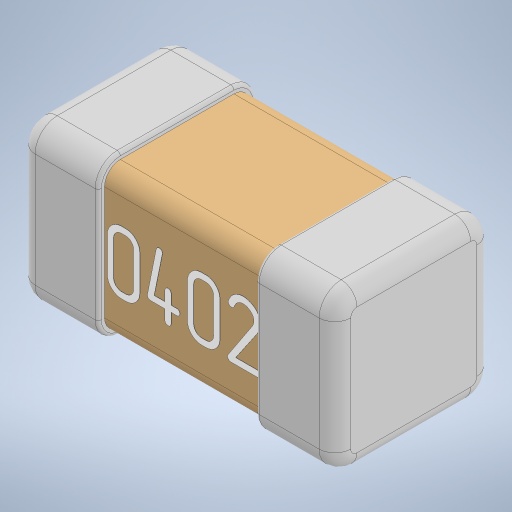
# Autodesk Inventor part: Discrete_Resistors_Ceramic_SMD
Saved by Autodesk Inventor 2024 (Build 280153000, 153)
## iProperties
Created: 2026-11-02
Part Number: Discrete_Resistors_Ceramic_SMD
Material: Generic
Document SubType Name: Modeling
Designer: danil
Density: 1 g/cm^3
Appearance: Default
Mass: 2.84071e-06 g
Surface Area: 0.00232509 cm^2
Volume: 2.84071e-06 cm^3
Author: danil
Autodesk Inventor part; units mm, degrees
ref_plane "YZ Plane" through (0, 0, 0) normal (1, 0, 0) x (0, 1, 0)
ref_plane "XZ Plane" through (0, 0, 0) normal (0, 1, 0) x (-1, 0, 0)
ref_plane "XY Plane" through (0, 0, 0) normal (0, 0, 1) x (1, 0, 0)
sketch "Sketch10" plane through (-0.11, 0.0625, 0) normal (0, 0, 1) x (1, 0, 0)
  line L0 (-0.37, -0.2925) -> (-0.37, 0.1675)
  line L1 (-0.37, 0.1675) -> (0.59, 0.1675)
  line L2 (0.59, 0.1675) -> (0.59, -0.2925)
  line L3 (0.59, -0.2925) -> (-0.37, -0.2925)
  line L4 (-0.37, 0.1675) -> (0.59, -0.2925) construction
  line L5 (0.59, 0.1675) -> (-0.37, -0.2925) construction
  point P0 (0.0299, -0.1069)
  point P1 (0.0299, 0)
  point P2 (0.11, -0.0625)
  point P3 (0.11, -0.0625)
  dimension "d78" = 0.46
  dimension "d79" = 0.96
  constraints: 12 end point, 3 perpendicular, 1 coincident, 1 horizontal alignment, 1 midpoint
  measures "d78" distance between parallel lines of L3 L1
  measures "d79" distance of L2.end L0.start
extrude "Ceramic_extrusion_1" add sketch "Sketch10" along normal blind 0.48
sketch "Sketch29" plane through (-0.11, 0.0625, 0) normal (0, 0, -1) x (-1, 0, 0)
  line L0 (-0.59, -0.2925) -> (-0.59, 0.1675) projected
  line L1 (0.37, -0.2925) -> (-0.59, -0.2925) projected
  line L2 (0.37, 0.1675) -> (0.37, -0.2925) projected
  line L3 (-0.59, 0.1675) -> (0.37, 0.1675) projected
  point P0 (-0.11, -0.0625)
extrude "Ceramic_extrusion_2" cut sketch "Sketch29" against normal blind 0.02
fillet "Ceramic_fillet_1" radius 0.05 4 edges at (0, 0.23, 0.02) (0, 0.23, 0.48) (0, -0.23, 0.02) (0, -0.23, 0.48)
sketch "Sketch35" plane through (0, 0, 0) normal (0, 0, 1) x (1, 0, 0)
  line L0 (-0.5, 0.25) -> (-0.25, 0.25)
  line L1 (-0.25, 0.25) -> (-0.25, -0.25)
  line L2 (-0.25, -0.25) -> (-0.5, -0.25)
  line L3 (-0.5, -0.25) -> (-0.5, 0.25)
  line L4 (0, 0.25) -> (0, -0.25) construction
  line L5 (0.5, 0.25) -> (0.25, 0.25)
  line L6 (0.25, 0.25) -> (0.25, -0.25)
  line L7 (0.25, -0.25) -> (0.5, -0.25)
  line L8 (0.5, -0.25) -> (0.5, 0.25)
  point P0 (0, 0)
  point P1 (-0.5, 0)
  point P2 (0.5, 0)
  point P3 (0, 0)
  dimension "d101" = 0.5
  dimension "d102" = 1
  dimension "d103" = 0.25
  constraints: 18 end point, 4 horizontal alignment, 4 symmetric about line, 3 midpoint, 2 parallel, 1 coincident, 1 horizontal, 1 perpendicular, 1 vertical
  measures "d101" distance of L2.end L0.start
  measures "d102" distance between parallel lines of L8 L3
  measures "d103" distance of L0.start L0.end
extrude "Contacts_extrusion_1" add sketch "Sketch35" along normal blind 0.5 separate body
sketch "Sketch36" plane through (-0.25, -0.25, 0) normal (1, 0, 0) x (0, 0, -1)
  line L0 (-0.48, 0.43) -> (-0.48, 0.07) projected
  line L1 (-0.07, 0.48) -> (-0.43, 0.48) projected
  line L2 (-0.02, 0.43) -> (-0.02, 0.07) projected
  line L3 (-0.07, 0.02) -> (-0.43, 0.02) projected
  arc A0 (-0.48, 0.07) -> (-0.43, 0.02) centre (-0.43, 0.07) ccw projected
  arc A1 (-0.43, 0.48) -> (-0.48, 0.43) centre (-0.43, 0.43) ccw projected
  arc A2 (-0.02, 0.43) -> (-0.07, 0.48) centre (-0.07, 0.43) ccw projected
  arc A3 (-0.07, 0.02) -> (-0.02, 0.07) centre (-0.07, 0.07) ccw projected
  point P0 (0, 0.25)
extrude "Contacts_extrusion_2" cut sketch "Sketch36" against normal blind 0.0833 bodies 2
sketch "Sketch37" plane through (0.25, -0.25, 0) normal (-1, 0, 0) x (0, 0, 1)
  line L0 (0.43, 0.48) -> (0.07, 0.48) projected
  arc A0 (0.48, 0.43) -> (0.43, 0.48) centre (0.43, 0.43) ccw projected
  line L1 (0.48, 0.07) -> (0.48, 0.43) projected
  arc A1 (0.43, 0.02) -> (0.48, 0.07) centre (0.43, 0.07) ccw projected
  line L2 (0.07, 0.02) -> (0.43, 0.02) projected
  arc A2 (0.02, 0.07) -> (0.07, 0.02) centre (0.07, 0.07) ccw projected
  line L3 (0.02, 0.43) -> (0.02, 0.07) projected
  arc A3 (0.07, 0.48) -> (0.02, 0.43) centre (0.07, 0.43) ccw projected
  point P0 (0, 0.25)
extrude "Contacts_extrusion_3" cut sketch "Sketch37" against normal blind 0.0833 bodies 2
sketch "Sketch38" plane through (0.5, -0.25, 0) normal (1, 0, 0) x (0, 0, -1)
  arc A0 (-0.02, 0.43) -> (-0.07, 0.48) centre (-0.07, 0.43) ccw construction
  line L0 (-0.02, 0.07) -> (-0.02, 0.43) construction
  arc A1 (-0.07, 0.02) -> (-0.02, 0.07) centre (-0.07, 0.07) ccw construction
  line L1 (-0.43, 0.02) -> (-0.07, 0.02) construction
  arc A2 (-0.48, 0.07) -> (-0.43, 0.02) centre (-0.43, 0.07) ccw construction
  line L2 (-0.48, 0.43) -> (-0.48, 0.07) construction
  arc A3 (-0.43, 0.48) -> (-0.48, 0.43) centre (-0.43, 0.43) ccw construction
  line L3 (-0.07, 0.48) -> (-0.43, 0.48) construction
  line L4 (-0.5, 0.43) -> (-0.5, 0.07)
  arc A4 (-0.5, 0.07) -> (-0.43, 0) centre (-0.43, 0.07) ccw
  line L5 (-0.43, 0) -> (-0.07, 0)
  arc A5 (-0.07, 0) -> (0, 0.07) centre (-0.07, 0.07) ccw
  line L6 (0, 0.07) -> (0, 0.43)
  arc A6 (0, 0.43) -> (-0.07, 0.5) centre (-0.07, 0.43) ccw
  line L7 (-0.07, 0.5) -> (-0.43, 0.5)
  arc A7 (-0.43, 0.5) -> (-0.5, 0.43) centre (-0.43, 0.43) ccw
  line L8 (0, 0) -> (0, 0.5) projected
  line L9 (0, 0.5) -> (-0.5, 0.5) projected
  line L10 (-0.5, 0) -> (-0.5, 0.5) projected
  line L11 (0, 0) -> (-0.5, 0) projected
  point P0 (0, 0.25)
  point P1 (-0.07, 0.5)
  point P2 (-0.5, 0.43)
  point P3 (-0.43, 0.5)
  point P4 (-0.5, 0.07)
  point P5 (-0.07, 0)
  dimension "d110" = 0.02
  constraints: 8 end point, 8 point on circle, 4 centre point, 7 other
  measures "d110" radial gap between concentric circles of A3 A7
extrude "Contacts_extrusion_4" cut sketch "Sketch38" against normal through all contours L10 L9 A7 | A4 L11 L10 | L9 L8 A6 | A5 L8 L11 bodies 2
fillet "Contacts_fillet_1" radius 0.05 16 edges at (-0.5, -0.2295, 0.4795) (-0.5, -0.25, 0.25) (-0.5, -0.2295, 0.0205) (-0.5, 0, 0) (-0.5, 0.2295, 0.0205) (-0.5, 0.25, 0.25) (-0.5, 0.2295, 0.4795) (-0.5, 0, 0.5) (0.5, 0.2295, 0.4795) (0.5, 0.25, 0.25) (0.5, 0.2295, 0.0205) (0.5, 0, 0) (0.5, -0.2295, 0.0205) (0.5, -0.25, 0.25) (0.5, -0.2295, 0.4795) (0.5, 0, 0.5)
fillet "Contacts_fillet_2" radius 0.01 16 edges at (-0.25, 0.2295, 0.4795) (-0.25, 0, 0.5) (-0.25, -0.2295, 0.4795) (-0.25, -0.25, 0.25) (-0.25, -0.2295, 0.0205) (-0.25, 0, 0) (-0.25, 0.2295, 0.0205) (-0.25, 0.25, 0.25) (0.25, 0.2295, 0.4795) (0.25, 0, 0.5) (0.25, -0.2295, 0.4795) (0.25, -0.25, 0.25) (0.25, -0.2295, 0.0205) (0.25, 0, 0) (0.25, 0.2295, 0.0205) (0.25, 0.25, 0.25)
sketch "Sketch14" plane through (-0.11, 0.0625, 0.48) normal (0, 0, 1) x (1, 0, 0)
  line L0 (-0.37, 0.1675) -> (0.59, 0.1675) construction
  line L1 (0.59, 0.1675) -> (0.59, -0.2925) construction
  line L2 (0.59, -0.2925) -> (-0.37, -0.2925) construction
  line L3 (-0.37, -0.2925) -> (-0.37, 0.1675) construction
  line L4 (-0.37, 0.1175) -> (-0.37, -0.2425) construction
  line L5 (0.59, -0.2425) -> (0.59, 0.1175) construction
  line L6 (-0.37, -0.2925) -> (0.59, -0.2925) projected
  line L7 (0.59, 0.1675) -> (-0.37, 0.1675) projected
  line L8 (-0.37, -0.2425) -> (0.59, -0.2425) projected
  line L9 (0.59, 0.1175) -> (-0.37, 0.1175) projected
  spline S0 degree 2 poles (-0.0274, -0.1177) (-0.0274, -0.1359) (-0.0534, -0.1621) (-0.0718, -0.1621) knots 0 0 0 1 2 2 2
  line L10 (-0.0718, -0.1621) -> (-0.0857, -0.1621)
  spline S1 degree 2 poles (-0.0857, -0.1621) (-0.1027, -0.1621) (-0.13, -0.1364) (-0.13, -0.1177) knots 0 0 0 1 2 2 2
  line L11 (-0.13, -0.1177) -> (-0.13, -0.0073)
  spline S2 degree 2 poles (-0.13, -0.0073) (-0.13, 0.0103) (-0.1043, 0.0369) (-0.0857, 0.0369) knots 0 0 0 1 2 2 2
  line L12 (-0.0857, 0.0369) -> (-0.0718, 0.0369)
  spline S3 degree 2 poles (-0.0718, 0.0369) (-0.0537, 0.0369) (-0.0274, 0.0111) (-0.0274, -0.0073) knots 0 0 0 1 2 2 2
  line L13 (-0.0274, -0.0073) -> (-0.0274, -0.1177)
  line L14 (-0.047, -0.1177) -> (-0.047, -0.0073)
  spline S4 degree 2 poles (-0.047, -0.0073) (-0.047, 0.0028) (-0.0616, 0.0174) (-0.0718, 0.0174) knots 0 0 0 1 2 2 2
  line L15 (-0.0718, 0.0174) -> (-0.0857, 0.0174)
  spline S5 degree 2 poles (-0.0857, 0.0174) (-0.0959, 0.0174) (-0.1104, 0.0029) (-0.1104, -0.0073) knots 0 0 0 1 2 2 2
  line L16 (-0.1104, -0.0073) -> (-0.1104, -0.1177)
  spline S6 degree 2 poles (-0.1104, -0.1177) (-0.1104, -0.1279) (-0.0955, -0.1426) (-0.0857, -0.1426) knots 0 0 0 1 2 2 2
  line L17 (-0.0857, -0.1426) -> (-0.0718, -0.1426)
  spline S7 degree 2 poles (-0.0718, -0.1426) (-0.0619, -0.1426) (-0.047, -0.1284) (-0.047, -0.1177) knots 0 0 0 1 2 2 2
  line L18 (0.0719, -0.1012) -> (0.0898, -0.1012)
  spline S8 degree 2 poles (0.0898, -0.1012) (0.0935, -0.1012) (0.0997, -0.1073) (0.0997, -0.1108) knots 0 0 0 1 2 2 2
  spline S9 degree 2 poles (0.0997, -0.1108) (0.0997, -0.1143) (0.0945, -0.1207) (0.0898, -0.1207) knots 0 0 0 1 2 2 2
  line L19 (0.0898, -0.1207) -> (0.0719, -0.1207)
  line L20 (0.0719, -0.1207) -> (0.0719, -0.1523)
  spline S10 degree 2 poles (0.0719, -0.1523) (0.0719, -0.1567) (0.0692, -0.1594) knots 0 0 0 1 1 1
  spline S11 degree 2 poles (0.0692, -0.1594) (0.0661, -0.1621) (0.0621, -0.1621) knots 0 0 0 1 1 1
  spline S12 degree 2 poles (0.0621, -0.1621) (0.0601, -0.1621) (0.0556, -0.1601) knots 0 0 0 1 1 1
  spline S13 degree 2 poles (0.0556, -0.1601) (0.0522, -0.1573) (0.0522, -0.1523) knots 0 0 0 1 1 1
  line L21 (0.0522, -0.1523) -> (0.0522, -0.1207)
  line L22 (0.0522, -0.1207) -> (0.0068, -0.1207)
  spline S14 degree 2 poles (0.0068, -0.1207) (0.0025, -0.1207) (-0.0031, -0.1152) (-0.0031, -0.1109) knots 0 0 0 1 2 2 2
  line L23 (-0.0031, -0.1109) -> (-0.003, -0.1092)
  line L24 (-0.003, -0.1092) -> (0.0246, 0.0285)
  spline S15 degree 2 poles (0.0246, 0.0285) (0.0252, 0.0329) (0.0285, 0.0351) knots 0 0 0 1 1 1
  line L25 (0.0285, 0.0351) -> (0.0339, 0.0369)
  spline S16 degree 2 poles (0.0339, 0.0369) (0.0382, 0.0369) (0.0443, 0.0316) (0.0443, 0.0276) knots 0 0 0 1 2 2 2
  line L26 (0.0443, 0.0276) -> (0.044, 0.0254)
  line L27 (0.044, 0.0254) -> (0.0181, -0.1012)
  line L28 (0.0181, -0.1012) -> (0.0522, -0.1012)
  line L29 (0.0522, -0.1012) -> (0.0522, -0.0694)
  spline S17 degree 2 poles (0.0522, -0.0694) (0.0522, -0.0662) (0.0579, -0.0597) (0.0621, -0.0597) knots 0 0 0 1 2 2 2
  spline S18 degree 2 poles (0.0621, -0.0597) (0.0655, -0.0597) (0.0719, -0.0649) (0.0719, -0.0694) knots 0 0 0 1 2 2 2
  line L30 (0.0719, -0.0694) -> (0.0719, -0.1012)
  spline S19 degree 2 poles (0.2264, -0.1177) (0.2264, -0.1359) (0.2004, -0.1621) (0.1819, -0.1621) knots 0 0 0 1 2 2 2
  line L31 (0.1819, -0.1621) -> (0.1681, -0.1621)
  spline S20 degree 2 poles (0.1681, -0.1621) (0.1511, -0.1621) (0.1237, -0.1364) (0.1237, -0.1177) knots 0 0 0 1 2 2 2
  line L32 (0.1237, -0.1177) -> (0.1237, -0.0073)
  spline S21 degree 2 poles (0.1237, -0.0073) (0.1237, 0.0103) (0.1494, 0.0369) (0.1681, 0.0369) knots 0 0 0 1 2 2 2
  line L33 (0.1681, 0.0369) -> (0.1819, 0.0369)
  spline S22 degree 2 poles (0.1819, 0.0369) (0.2001, 0.0369) (0.2264, 0.0111) (0.2264, -0.0073) knots 0 0 0 1 2 2 2
  line L34 (0.2264, -0.0073) -> (0.2264, -0.1177)
  line L35 (0.2068, -0.1177) -> (0.2068, -0.0073)
  spline S23 degree 2 poles (0.2068, -0.0073) (0.2068, 0.0028) (0.1921, 0.0174) (0.1819, 0.0174) knots 0 0 0 1 2 2 2
  line L36 (0.1819, 0.0174) -> (0.1681, 0.0174)
  spline S24 degree 2 poles (0.1681, 0.0174) (0.1579, 0.0174) (0.1434, 0.0029) (0.1434, -0.0073) knots 0 0 0 1 2 2 2
  line L37 (0.1434, -0.0073) -> (0.1434, -0.1177)
  spline S25 degree 2 poles (0.1434, -0.1177) (0.1434, -0.1279) (0.1583, -0.1426) (0.1681, -0.1426) knots 0 0 0 1 2 2 2
  line L38 (0.1681, -0.1426) -> (0.1819, -0.1426)
  spline S26 degree 2 poles (0.1819, -0.1426) (0.1918, -0.1426) (0.2068, -0.1284) (0.2068, -0.1177) knots 0 0 0 1 2 2 2
  line L39 (0.3431, -0.1621) -> (0.2605, -0.1621)
  spline S27 degree 2 poles (0.2605, -0.1621) (0.2568, -0.1621) (0.2534, -0.1588) knots 0 0 0 1 1 1
  spline S28 degree 2 poles (0.2534, -0.1588) (0.2508, -0.1557) (0.2508, -0.1517) knots 0 0 0 1 1 1
  spline S29 degree 2 poles (0.2508, -0.1517) (0.2508, -0.1489) (0.2519, -0.1471) knots 0 0 0 1 1 1
  line L40 (0.2519, -0.1471) -> (0.328, -0.0322)
  line L41 (0.328, -0.0322) -> (0.3308, -0.0269)
  line L42 (0.3308, -0.0269) -> (0.3327, -0.0225)
  spline S30 degree 2 poles (0.3327, -0.0225) (0.3342, -0.018) (0.3342, -0.0132) knots 0 0 0 1 1 1
  spline S31 degree 2 poles (0.3342, -0.0132) (0.3342, -0.0006) (0.324, 0.008) knots 0 0 0 1 1 1
  spline S32 degree 2 poles (0.324, 0.008) (0.3193, 0.0122) (0.3068, 0.0173) (0.3004, 0.0173) knots 0 0 0 1 2 2 2
  spline S33 degree 2 poles (0.3004, 0.0173) (0.2918, 0.0173) (0.2769, 0.0077) (0.2717, -0.005) knots 0 0 0 1 2 2 2
  spline S34 degree 2 poles (0.2717, -0.005) (0.271, -0.0074) (0.2685, -0.0092) knots 0 0 0 1 1 1
  spline S35 degree 2 poles (0.2685, -0.0092) (0.2664, -0.0102) (0.2636, -0.0108) knots 0 0 0 1 1 1
  spline S36 degree 2 poles (0.2636, -0.0108) (0.2592, -0.0108) (0.253, -0.0055) (0.253, -0.0006) knots 0 0 0 1 2 2 2
  line L43 (0.253, -0.0006) -> (0.2534, 0.0019)
  spline S37 degree 2 poles (0.2534, 0.0019) (0.2596, 0.0199) (0.2728, 0.0289) knots 0 0 0 1 1 1
  spline S38 degree 2 poles (0.2728, 0.0289) (0.2844, 0.0371) (0.2998, 0.0371) knots 0 0 0 1 1 1
  spline S39 degree 2 poles (0.2998, 0.0371) (0.3206, 0.0371) (0.3381, 0.0177) knots 0 0 0 1 1 1
  spline S40 degree 2 poles (0.3381, 0.0177) (0.3543, 0.0077) (0.3543, -0.0133) knots 0 0 0 1 1 1
  spline S41 degree 2 poles (0.3543, -0.0133) (0.3543, -0.0204) (0.3499, -0.0343) (0.3444, -0.0433) knots 0 0 0 1 2 2 2
  line L44 (0.3444, -0.0433) -> (0.2765, -0.1426)
  line L45 (0.2765, -0.1426) -> (0.3431, -0.1426)
  spline S42 degree 2 poles (0.3431, -0.1426) (0.3468, -0.1426) (0.353, -0.1486) (0.353, -0.1522) knots 0 0 0 1 2 2 2
  spline S43 degree 2 poles (0.353, -0.1522) (0.353, -0.1557) (0.3478, -0.1621) (0.3431, -0.1621) knots 0 0 0 1 2 2 2
  dimension "d37" = 0.48
  dimension "d38" = 0
  constraints: 4 collinear, 2 other
extrude "Text_extrusion_1" add sketch "Sketch14" along normal blind 0.001 separate body
sketch "Sketch23" plane through (-0.11, 0.0625, 0.481) normal (0, 0, 1) x (1, 0, 0)
  line L0 (0.2605, -0.1621) -> (0.3431, -0.1621) projected
  line L1 (0.3431, -0.1426) -> (0.2765, -0.1426) projected
  line L2 (0.2765, -0.1426) -> (0.3444, -0.0433) projected
  spline S0 degree 2 poles (0.3543, -0.0133) (0.3543, 0.0077) (0.3381, 0.0177) knots 0 0 0 1 1 1 projected
  spline S1 degree 2 poles (0.3381, 0.0177) (0.3206, 0.0371) (0.2998, 0.0371) knots 0 0 0 1 1 1 projected
  line L3 (0.2534, 0.0019) -> (0.253, -0.0006) projected
  line L4 (0.3327, -0.0225) -> (0.3308, -0.0269) projected
  line L5 (0.3308, -0.0269) -> (0.328, -0.0322) projected
  line L6 (0.328, -0.0322) -> (0.2519, -0.1471) projected
  spline S2 degree 4 poles (0.2998, 0.0371) (0.3103, 0.0371) (0.3313, 0.0305) (0.3486, 0.019) (0.3543, -0.0025) (0.3543, -0.0133) knots 0 0 0 0 0 0.5 1 1 1 1 1
  point P0 (0.11, -0.0625)
  constraints: 19 other
extrude "Text_extrusion_2" add sketch "Sketch23" against normal blind 0.001 bodies 3
equation "\"vL\" = 1"
equation "\"vW\" = 0.5"
equation "\"vH\" = 0.5"
equation "\"vl1\" = 0.25"
equation "\"vS\" = 0.02"
equation "\"vr1\" = 0.05"
equation "\"vr2\" = 0.05"
equation "\"vl2\" = 0.25"
equation "\"vFont\" = 0.4"
equation "\"vl1s\" = 0.05"
